Autodesk Fusion 360 part; units mm, degrees
(part 7 of 8)
sketch "Front roller support | profile (2)" plane through (0, 0, 14) normal (0, 0, 1) x (1, 0, 0) in component "11:1 twin-disc elbow | original geometry"
  line L0 (38, 0) -> (37.817, 3.7247)
  line L1 (37.817, 3.7247) -> (37.2698, 7.4134)
  line L2 (37.2698, 7.4134) -> (36.3637, 11.0308)
  line L3 (36.3637, 11.0308) -> (35.1074, 14.542)
  line L4 (35.1074, 14.542) -> (33.513, 17.9131)
  line L5 (33.513, 17.9131) -> (31.5958, 21.1117)
  line L6 (31.5958, 21.1117) -> (29.3744, 24.1069)
  line L7 (29.3744, 24.1069) -> (26.8701, 26.8701)
  line L8 (26.8701, 26.8701) -> (24.1069, 29.3744)
  line L9 (24.1069, 29.3744) -> (21.1117, 31.5958)
  line L10 (21.1117, 31.5958) -> (17.9131, 33.513)
  line L11 (17.9131, 33.513) -> (14.542, 35.1074)
  line L12 (14.542, 35.1074) -> (11.0308, 36.3637)
  line L13 (11.0308, 36.3637) -> (7.4134, 37.2698)
  line L14 (7.4134, 37.2698) -> (3.7247, 37.817)
  line L15 (3.7247, 37.817) -> (0, 38)
  line L16 (0, 38) -> (-3.7247, 37.817)
  line L17 (-3.7247, 37.817) -> (-7.4134, 37.2698)
  line L18 (-7.4134, 37.2698) -> (-11.0308, 36.3637)
  line L19 (-11.0308, 36.3637) -> (-14.542, 35.1074)
  line L20 (-14.542, 35.1074) -> (-17.9131, 33.513)
  line L21 (-17.9131, 33.513) -> (-21.1117, 31.5958)
  line L22 (-21.1117, 31.5958) -> (-24.1069, 29.3744)
  line L23 (-24.1069, 29.3744) -> (-26.8701, 26.8701)
  line L24 (-26.8701, 26.8701) -> (-29.3744, 24.1069)
  line L25 (-29.3744, 24.1069) -> (-31.5958, 21.1117)
  line L26 (-31.5958, 21.1117) -> (-33.513, 17.9131)
  line L27 (-33.513, 17.9131) -> (-35.1074, 14.542)
  line L28 (-35.1074, 14.542) -> (-36.3637, 11.0308)
  line L29 (-36.3637, 11.0308) -> (-37.2698, 7.4134)
  line L30 (-37.2698, 7.4134) -> (-37.817, 3.7247)
  line L31 (-37.817, 3.7247) -> (-38, 0)
  line L32 (-38, 0) -> (-37.817, -3.7247)
  line L33 (-37.817, -3.7247) -> (-37.2698, -7.4134)
  line L34 (-37.2698, -7.4134) -> (-36.3637, -11.0308)
  line L35 (-36.3637, -11.0308) -> (-35.1074, -14.542)
  line L36 (-35.1074, -14.542) -> (-33.513, -17.9131)
  line L37 (-33.513, -17.9131) -> (-31.5958, -21.1117)
  line L38 (-31.5958, -21.1117) -> (-29.3744, -24.1069)
  line L39 (-29.3744, -24.1069) -> (-26.8701, -26.8701)
  line L40 (-26.8701, -26.8701) -> (-24.1069, -29.3744)
  line L41 (-24.1069, -29.3744) -> (-21.1117, -31.5958)
  line L42 (-21.1117, -31.5958) -> (-17.9131, -33.513)
  line L43 (-17.9131, -33.513) -> (-14.542, -35.1074)
  line L44 (-14.542, -35.1074) -> (-11.0308, -36.3637)
  line L45 (-11.0308, -36.3637) -> (-7.4134, -37.2698)
  line L46 (-7.4134, -37.2698) -> (-3.7247, -37.817)
  line L47 (-3.7247, -37.817) -> (0, -38)
  line L48 (0, -38) -> (3.7247, -37.817)
  line L49 (3.7247, -37.817) -> (7.4134, -37.2698)
  line L50 (7.4134, -37.2698) -> (11.0308, -36.3637)
  line L51 (11.0308, -36.3637) -> (14.542, -35.1074)
  line L52 (14.542, -35.1074) -> (17.9131, -33.513)
  line L53 (17.9131, -33.513) -> (21.1117, -31.5958)
  line L54 (21.1117, -31.5958) -> (24.1069, -29.3744)
  line L55 (24.1069, -29.3744) -> (26.8701, -26.8701)
  line L56 (26.8701, -26.8701) -> (29.3744, -24.1069)
  line L57 (29.3744, -24.1069) -> (31.5958, -21.1117)
  line L58 (31.5958, -21.1117) -> (33.513, -17.9131)
  line L59 (33.513, -17.9131) -> (35.1074, -14.542)
  line L60 (35.1074, -14.542) -> (36.3637, -11.0308)
  line L61 (36.3637, -11.0308) -> (37.2698, -7.4134)
  line L62 (37.2698, -7.4134) -> (37.817, -3.7247)
  line L63 (37.817, -3.7247) -> (38, 0)
  circle A0 centre (0, 0) radius 21.1
  circle A1 centre (36, 0) radius 1.6
  circle A2 centre (18, 31.1769) radius 1.6
  circle A3 centre (-18, 31.1769) radius 1.6
  circle A4 centre (-36, 0) radius 1.6
  circle A5 centre (-18, -31.1769) radius 1.6
  circle A6 centre (18, -31.1769) radius 1.6
extrude "Front roller support'" add sketch "Front roller support | profile (2)" along normal blind 3 separate body makes body 323 in component "11:1 twin-disc elbow | original geometry"
ref_plane "WorkPlane4" through (0, 0, -6) normal (0, 0, 1) x (1, 0, 0) in component "11:1 twin-disc elbow | original geometry"
sketch "Cycloidal disc A | 11 lobes | profile (2)" plane through (0, 0, -6) normal (0, 0, 1) x (1, 0, 0) in component "11:1 twin-disc elbow | original geometry"
  spline S0 degree 3 poles (25.9, 0) (25.9, 0.3482) (25.956, 1.0447) (26.1483, 1.9285) (26.3602, 2.6329) (26.553, 3.2163) (26.7189, 3.739) (26.8573, 4.2438) (26.9654, 4.7563) (27.0369, 5.2891) (27.0643, 5.8448) (27.0401, 6.4189) (26.9592, 7.0019) (26.8198, 7.5814) (26.6238, 8.1443) (26.3766, 8.6784) (26.0866, 9.1745) (25.7631, 9.6272) (25.4149, 10.0367) (25.0469, 10.4094) (24.6576, 10.7592) (24.2354, 11.1092) (23.7578, 11.4958) (23.1987, 11.9738) (22.5591, 12.6134) (21.9237, 13.4468) (21.4295, 14.3711) (21.1135, 15.2186) (20.9109, 15.9257) (20.7576, 16.5207) (20.6146, 17.0501) (20.4582, 17.5496) (20.272, 18.0392) (20.0442, 18.5261) (19.7667, 19.0083) (19.436, 19.4782) (19.0528, 19.9249) (18.6222, 20.3371) (18.153, 20.7047) (17.6562, 21.0204) (17.1441, 21.2809) (16.6272, 21.4869) (16.1129, 21.6431) (15.6018, 21.7577) (15.0851, 21.8415) (14.5408, 21.9077) (13.93, 21.9747) (13.2012, 22.0746) (12.3174, 22.2668) (11.3322, 22.6244) (10.4168, 23.1348) (9.6927, 23.6768) (9.14, 24.1622) (8.6894, 24.5799) (8.2829, 24.948) (7.8812, 25.2836) (7.4599, 25.5948) (7.005, 25.8812) (6.5109, 26.1369) (5.9786, 26.3534) (5.4147, 26.522) (4.8297, 26.6359) (4.2362, 26.6914) (3.6476, 26.6885) (3.076, 26.6308) (2.5298, 26.5246) (2.0126, 26.378) (1.5207, 26.1981) (1.0408, 25.9892) (0.547, 25.7506) (-0.003, 25.4768) (-0.6701, 25.1668) (-1.5176, 24.8507) (-2.5397, 24.6188) (-3.5857, 24.5533) (-4.4879, 24.6179) (-5.2153, 24.7274) (-5.8202, 24.8351) (-6.3611, 24.925) (-6.8805, 24.9902) (-7.4031, 25.0242) (-7.9407, 25.0192) (-8.4946, 24.9672) (-9.0594, 24.8615) (-9.625, 24.6985) (-10.1787, 24.478) (-10.708, 24.2039) (-11.2016, 23.8832) (-11.6513, 23.5256) (-12.0534, 23.141) (-12.4091, 22.738) (-12.7257, 22.3207) (-13.0165, 21.8856) (-13.3029, 21.4179) (-13.6176, 20.8902) (-14.0112, 20.2687) (-14.5532, 19.5446) (-15.2877, 18.797) (-16.1322, 18.1764) (-16.9261, 17.7429) (-17.5972, 17.4418) (-18.1644, 17.2054) (-18.6681, 16.9885) (-19.1402, 16.7626) (-19.5983, 16.5086) (-20.0478, 16.2138) (-20.4856, 15.8705) (-20.9037, 15.4763) (-21.2913, 15.0334) (-21.638, 14.5486) (-21.935, 14.0318) (-22.1769, 13.4952) (-22.3618, 12.9512) (-22.4921, 12.4103) (-22.5736, 11.8789) (-22.6143, 11.3567) (-22.6237, 10.8334) (-22.6118, 10.2851) (-22.5912, 9.6711) (-22.5863, 8.9355) (-22.6508, 8.0333) (-22.8645, 7.0073) (-23.2394, 6.0285) (-23.6729, 5.2347) (-24.0747, 4.6185) (-24.424, 4.1131) (-24.7305, 3.6583) (-25.0055, 3.213) (-25.2536, 2.7517) (-25.4723, 2.2606) (-25.6551, 1.7351) (-25.7937, 1.1775) (-25.8803, 0.5953) (-25.9098, 0) (-25.8803, -0.5953) (-25.7937, -1.1775) (-25.6551, -1.7351) (-25.4723, -2.2606) (-25.2536, -2.7517) (-25.0055, -3.213) (-24.7305, -3.6583) (-24.424, -4.1131) (-24.0747, -4.6185) (-23.6729, -5.2347) (-23.2394, -6.0285) (-22.8645, -7.0073) (-22.6508, -8.0333) (-22.5863, -8.9355) (-22.5912, -9.6711) (-22.6118, -10.2851) (-22.6237, -10.8334) (-22.6143, -11.3567) (-22.5736, -11.8789) (-22.4921, -12.4103) (-22.3618, -12.9512) (-22.1769, -13.4952) (-21.935, -14.0318) (-21.638, -14.5486) (-21.2913, -15.0334) (-20.9037, -15.4763) (-20.4856, -15.8705) (-20.0478, -16.2138) (-19.5983, -16.5086) (-19.1402, -16.7626) (-18.6681, -16.9885) (-18.1644, -17.2054) (-17.5972, -17.4418) (-16.9261, -17.7429) (-16.1322, -18.1764) (-15.2877, -18.797) (-14.5532, -19.5446) (-14.0112, -20.2687) (-13.6176, -20.8902) (-13.3029, -21.4179) (-13.0165, -21.8856) (-12.7257, -22.3207) (-12.4091, -22.738) (-12.0534, -23.141) (-11.6513, -23.5256) (-11.2016, -23.8832) (-10.708, -24.2039) (-10.1787, -24.478) (-9.625, -24.6985) (-9.0594, -24.8615) (-8.4946, -24.9672) (-7.9407, -25.0192) (-7.4031, -25.0242) (-6.8805, -24.9902) (-6.3611, -24.925) (-5.8202, -24.8351) (-5.2153, -24.7274) (-4.4879, -24.6179) (-3.5857, -24.5533) (-2.5397, -24.6188) (-1.5176, -24.8507) (-0.6701, -25.1668) (-0.003, -25.4768) (0.547, -25.7506) (1.0408, -25.9892) (1.5207, -26.1981) (2.0126, -26.378) (2.5298, -26.5246) (3.076, -26.6308) (3.6476, -26.6885) (4.2362, -26.6914) (4.8297, -26.6359) (5.4147, -26.522) (5.9786, -26.3534) (6.5109, -26.1369) (7.005, -25.8812) (7.4599, -25.5948) (7.8812, -25.2836) (8.2829, -24.948) (8.6894, -24.5799) (9.14, -24.1622) (9.6927, -23.6768) (10.4168, -23.1348) (11.3322, -22.6244) (12.3174, -22.2668) (13.2012, -22.0746) (13.93, -21.9747) (14.5408, -21.9077) (15.0851, -21.8415) (15.6018, -21.7577) (16.1129, -21.6431) (16.6272, -21.4869) (17.1441, -21.2809) (17.6562, -21.0204) (18.153, -20.7047) (18.6222, -20.3371) (19.0528, -19.9249) (19.436, -19.4782) (19.7667, -19.0083) (20.0442, -18.5261) (20.272, -18.0392) (20.4582, -17.5496) (20.6146, -17.0501) (20.7576, -16.5207) (20.9109, -15.9257) (21.1135, -15.2186) (21.4295, -14.3711) (21.9237, -13.4468) (22.5591, -12.6134) (23.1987, -11.9738) (23.7578, -11.4958) (24.2354, -11.1092) (24.6576, -10.7592) (25.0469, -10.4094) (25.4149, -10.0367) (25.7631, -9.6272) (26.0866, -9.1745) (26.3766, -8.6784) (26.6238, -8.1443) (26.8198, -7.5814) (26.9592, -7.0019) (27.0401, -6.4189) (27.0643, -5.8448) (27.0369, -5.2891) (26.9654, -4.7563) (26.8573, -4.2438) (26.7189, -3.739) (26.553, -3.2163) (26.3602, -2.6329) (26.1483, -1.9285) (25.956, -1.0447) (25.9, -0.3482) (25.9, 0) knots 3 3 3 3 4 5 6 7 8 9 10 11 12 13 14 15 16 17 18 19 20 21 22 23 24 25 26 27 28 29 30 31 32 33 34 35 36 37 38 39 40 41 42 43 44 45 46 47 48 49 50 51 52 53 54 55 56 57 58 59 60 61 62 63 64 65 66 67 68 69 70 71 72 73 74 75 76 77 78 79 80 81 82 83 84 85 86 87 88 89 90 91 92 93 94 95 96 97 98 99 100 101 102 103 104 105 106 107 108 109 110 111 112 113 114 115 116 117 118 119 120 121 122 123 124 125 126 127 128 129 130 131 132 133 134 135 136 137 138 139 140 141 142 143 144 145 146 147 148 149 150 151 152 153 154 155 156 157 158 159 160 161 162 163 164 165 166 167 168 169 170 171 172 173 174 175 176 177 178 179 180 181 182 183 184 185 186 187 188 189 190 191 192 193 194 195 196 197 198 199 200 201 202 203 204 205 206 207 208 209 210 211 212 213 214 215 216 217 218 219 220 221 222 223 224 225 226 227 228 229 230 231 232 233 234 235 236 237 238 239 240 241 242 243 244 245 246 247 248 249 250 251 252 253 254 255 256 257 258 259 260 261 262 263 264 265 266 267 267 267 267
  circle A0 centre (1, 0) radius 9.6
  circle A1 centre (19, 0) radius 2.65
  circle A2 centre (10, 15.5885) radius 2.65
  circle A3 centre (-8, 15.5885) radius 2.65
  circle A4 centre (-17, 0) radius 2.65
  circle A5 centre (-8, -15.5885) radius 2.65
  circle A6 centre (10, -15.5885) radius 2.65
extrude "Cycloidal disc A | 11 lobes'" add sketch "Cycloidal disc A | 11 lobes | profile (2)" along normal blind 5 separate body makes body 324 in component "11:1 twin-disc elbow | original geometry"
ref_plane "WorkPlane5" through (0, 0, -6) normal (0, 0, 1) x (1, 0, 0) in component "11:1 twin-disc elbow | original geometry"
sketch "Eccentric bearing A outer race | profile (2)" plane through (0, 0, -6) normal (0, 0, 1) x (1, 0, 0) in component "11:1 twin-disc elbow | original geometry"
  circle A0 centre (1, 0) radius 9.5
  circle A1 centre (1, 0) radius 8.5
extrude "Eccentric bearing A outer race'" add sketch "Eccentric bearing A outer race | profile (2)" along normal blind 5 separate body makes body 325 in component "11:1 twin-disc elbow | original geometry"
ref_plane "WorkPlane6" through (0, 0, -6) normal (0, 0, 1) x (1, 0, 0) in component "11:1 twin-disc elbow | original geometry"
sketch "Eccentric bearing A inner race | profile (2)" plane through (0, 0, -6) normal (0, 0, 1) x (1, 0, 0) in component "11:1 twin-disc elbow | original geometry"
  circle A0 centre (1, 0) radius 6
  circle A1 centre (1, 0) radius 5
extrude "Eccentric bearing A inner race'" add sketch "Eccentric bearing A inner race | profile (2)" along normal blind 5 separate body makes body 326 in component "11:1 twin-disc elbow | original geometry"
ref_plane "WorkPlane7" through (0, 0, -5.85) normal (0, 0, 1) x (1, 0, 0) in component "11:1 twin-disc elbow | original geometry"
sketch "Eccentric bearing A shield | profile (2)" plane through (0, 0, -5.85) normal (0, 0, 1) x (1, 0, 0) in component "11:1 twin-disc elbow | original geometry"
  circle A0 centre (1, 0) radius 8.5
  circle A1 centre (1, 0) radius 6
extrude "Eccentric bearing A shield'" add sketch "Eccentric bearing A shield | profile (2)" along normal blind 4.7 separate body makes body 327 in component "11:1 twin-disc elbow | original geometry"
ref_plane "WorkPlane8" through (0, 0, -6) normal (0, 0, 1) x (1, 0, 0) in component "11:1 twin-disc elbow | original geometry"
sketch "Steel eccentric cam A | profile (2)" plane through (0, 0, -6) normal (0, 0, 1) x (1, 0, 0) in component "11:1 twin-disc elbow | original geometry"
  circle A0 centre (1, 0) radius 5
  circle A1 centre (1, 0) radius 3
extrude "Steel eccentric cam A'" add sketch "Steel eccentric cam A | profile (2)" along normal blind 5 separate body makes body 328 in component "11:1 twin-disc elbow | original geometry"
ref_plane "WorkPlane9" through (0, 0, 1) normal (0, 0, 1) x (1, 0, 0) in component "11:1 twin-disc elbow | original geometry"
sketch "Cycloidal disc B | 11 lobes | profile (2)" plane through (0, 0, 1) normal (0, 0, 1) x (1, 0, 0) in component "11:1 twin-disc elbow | original geometry"
  spline S0 degree 3 poles (22.8914, -7.0151) (22.9895, -6.681) (23.2394, -6.0285) (23.6729, -5.2347) (24.0747, -4.6185) (24.424, -4.1131) (24.7305, -3.6583) (25.0055, -3.213) (25.2536, -2.7517) (25.4723, -2.2606) (25.6551, -1.7351) (25.7937, -1.1775) (25.8803, -0.5953) (25.9098, 0) (25.8803, 0.5953) (25.7937, 1.1775) (25.6551, 1.7351) (25.4723, 2.2606) (25.2536, 2.7517) (25.0055, 3.213) (24.7305, 3.6583) (24.424, 4.1131) (24.0747, 4.6185) (23.6729, 5.2347) (23.2394, 6.0285) (22.8645, 7.0073) (22.6508, 8.0333) (22.5863, 8.9355) (22.5912, 9.6711) (22.6118, 10.2851) (22.6237, 10.8334) (22.6143, 11.3567) (22.5736, 11.8789) (22.4921, 12.4103) (22.3618, 12.9512) (22.1769, 13.4952) (21.935, 14.0318) (21.638, 14.5486) (21.2913, 15.0334) (20.9037, 15.4763) (20.4856, 15.8705) (20.0478, 16.2138) (19.5983, 16.5086) (19.1402, 16.7626) (18.6681, 16.9885) (18.1644, 17.2054) (17.5972, 17.4418) (16.9261, 17.7429) (16.1322, 18.1764) (15.2877, 18.797) (14.5532, 19.5446) (14.0112, 20.2687) (13.6176, 20.8902) (13.3029, 21.4179) (13.0165, 21.8856) (12.7257, 22.3207) (12.4091, 22.738) (12.0534, 23.141) (11.6513, 23.5256) (11.2016, 23.8832) (10.708, 24.2039) (10.1787, 24.478) (9.625, 24.6985) (9.0594, 24.8615) (8.4946, 24.9672) (7.9407, 25.0192) (7.4031, 25.0242) (6.8805, 24.9902) (6.3611, 24.925) (5.8202, 24.8351) (5.2153, 24.7274) (4.4879, 24.6179) (3.5857, 24.5533) (2.5397, 24.6188) (1.5176, 24.8507) (0.6701, 25.1668) (0.003, 25.4768) (-0.547, 25.7506) (-1.0408, 25.9892) (-1.5207, 26.1981) (-2.0126, 26.378) (-2.5298, 26.5246) (-3.076, 26.6308) (-3.6476, 26.6885) (-4.2362, 26.6914) (-4.8297, 26.6359) (-5.4147, 26.522) (-5.9786, 26.3534) (-6.5109, 26.1369) (-7.005, 25.8812) (-7.4599, 25.5948) (-7.8812, 25.2836) (-8.2829, 24.948) (-8.6894, 24.5799) (-9.14, 24.1622) (-9.6927, 23.6768) (-10.4168, 23.1348) (-11.3322, 22.6244) (-12.3174, 22.2668) (-13.2012, 22.0746) (-13.93, 21.9747) (-14.5408, 21.9077) (-15.0851, 21.8415) (-15.6018, 21.7577) (-16.1129, 21.6431) (-16.6272, 21.4869) (-17.1441, 21.2809) (-17.6562, 21.0204) (-18.153, 20.7047) (-18.6222, 20.3371) (-19.0528, 19.9249) (-19.436, 19.4782) (-19.7667, 19.0083) (-20.0442, 18.5261) (-20.272, 18.0392) (-20.4582, 17.5496) (-20.6146, 17.0501) (-20.7576, 16.5207) (-20.9109, 15.9257) (-21.1135, 15.2186) (-21.4295, 14.3711) (-21.9237, 13.4468) (-22.5591, 12.6134) (-23.1987, 11.9738) (-23.7578, 11.4958) (-24.2354, 11.1092) (-24.6576, 10.7592) (-25.0469, 10.4094) (-25.4149, 10.0367) (-25.7631, 9.6272) (-26.0866, 9.1745) (-26.3766, 8.6784) (-26.6238, 8.1443) (-26.8198, 7.5814) (-26.9592, 7.0019) (-27.0401, 6.4189) (-27.0643, 5.8448) (-27.0369, 5.2891) (-26.9654, 4.7563) (-26.8573, 4.2438) (-26.7189, 3.739) (-26.553, 3.2163) (-26.3602, 2.6329) (-26.1483, 1.9285) (-25.956, 1.0447) (-25.872, 0) (-25.956, -1.0447) (-26.1483, -1.9285) (-26.3602, -2.6329) (-26.553, -3.2163) (-26.7189, -3.739) (-26.8573, -4.2438) (-26.9654, -4.7563) (-27.0369, -5.2891) (-27.0643, -5.8448) (-27.0401, -6.4189) (-26.9592, -7.0019) (-26.8198, -7.5814) (-26.6238, -8.1443) (-26.3766, -8.6784) (-26.0866, -9.1745) (-25.7631, -9.6272) (-25.4149, -10.0367) (-25.0469, -10.4094) (-24.6576, -10.7592) (-24.2354, -11.1092) (-23.7578, -11.4958) (-23.1987, -11.9738) (-22.5591, -12.6134) (-21.9237, -13.4468) (-21.4295, -14.3711) (-21.1135, -15.2186) (-20.9109, -15.9257) (-20.7576, -16.5207) (-20.6146, -17.0501) (-20.4582, -17.5496) (-20.272, -18.0392) (-20.0442, -18.5261) (-19.7667, -19.0083) (-19.436, -19.4782) (-19.0528, -19.9249) (-18.6222, -20.3371) (-18.153, -20.7047) (-17.6562, -21.0204) (-17.1441, -21.2809) (-16.6272, -21.4869) (-16.1129, -21.6431) (-15.6018, -21.7577) (-15.0851, -21.8415) (-14.5408, -21.9077) (-13.93, -21.9747) (-13.2012, -22.0746) (-12.3174, -22.2668) (-11.3322, -22.6244) (-10.4168, -23.1348) (-9.6927, -23.6768) (-9.14, -24.1622) (-8.6894, -24.5799) (-8.2829, -24.948) (-7.8812, -25.2836) (-7.4599, -25.5948) (-7.005, -25.8812) (-6.5109, -26.1369) (-5.9786, -26.3534) (-5.4147, -26.522) (-4.8297, -26.6359) (-4.2362, -26.6914) (-3.6476, -26.6885) (-3.076, -26.6308) (-2.5298, -26.5246) (-2.0126, -26.378) (-1.5207, -26.1981) (-1.0408, -25.9892) (-0.547, -25.7506) (0.003, -25.4768) (0.6701, -25.1668) (1.5176, -24.8507) (2.5397, -24.6188) (3.5857, -24.5533) (4.4879, -24.6179) (5.2153, -24.7274) (5.8202, -24.8351) (6.3611, -24.925) (6.8805, -24.9902) (7.4031, -25.0242) (7.9407, -25.0192) (8.4946, -24.9672) (9.0594, -24.8615) (9.625, -24.6985) (10.1787, -24.478) (10.708, -24.2039) (11.2016, -23.8832) (11.6513, -23.5256) (12.0534, -23.141) (12.4091, -22.738) (12.7257, -22.3207) (13.0165, -21.8856) (13.3029, -21.4179) (13.6176, -20.8902) (14.0112, -20.2687) (14.5532, -19.5446) (15.2877, -18.797) (16.1322, -18.1764) (16.9261, -17.7429) (17.5972, -17.4418) (18.1644, -17.2054) (18.6681, -16.9885) (19.1402, -16.7626) (19.5983, -16.5086) (20.0478, -16.2138) (20.4856, -15.8705) (20.9037, -15.4763) (21.2913, -15.0334) (21.638, -14.5486) (21.935, -14.0318) (22.1769, -13.4952) (22.3618, -12.9512) (22.4921, -12.4103) (22.5736, -11.8789) (22.6143, -11.3567) (22.6237, -10.8334) (22.6118, -10.2851) (22.5912, -9.6711) (22.5863, -8.9355) (22.6508, -8.0333) (22.7933, -7.3493) (22.8914, -7.0151) knots 3 3 3 3 4 5 6 7 8 9 10 11 12 13 14 15 16 17 18 19 20 21 22 23 24 25 26 27 28 29 30 31 32 33 34 35 36 37 38 39 40 41 42 43 44 45 46 47 48 49 50 51 52 53 54 55 56 57 58 59 60 61 62 63 64 65 66 67 68 69 70 71 72 73 74 75 76 77 78 79 80 81 82 83 84 85 86 87 88 89 90 91 92 93 94 95 96 97 98 99 100 101 102 103 104 105 106 107 108 109 110 111 112 113 114 115 116 117 118 119 120 121 122 123 124 125 126 127 128 129 130 131 132 133 134 135 136 137 138 139 140 141 142 143 144 145 146 147 148 149 150 151 152 153 154 155 156 157 158 159 160 161 162 163 164 165 166 167 168 169 170 171 172 173 174 175 176 177 178 179 180 181 182 183 184 185 186 187 188 189 190 191 192 193 194 195 196 197 198 199 200 201 202 203 204 205 206 207 208 209 210 211 212 213 214 215 216 217 218 219 220 221 222 223 224 225 226 227 228 229 230 231 232 233 234 235 236 237 238 239 240 241 242 243 244 245 246 247 248 249 250 251 252 253 254 255 256 257 258 259 260 261 262 263 264 265 266 267 267 267 267
  circle A0 centre (-1, 0) radius 9.6
  circle A1 centre (17, 0) radius 2.65
  circle A2 centre (8, 15.5885) radius 2.65
  circle A3 centre (-10, 15.5885) radius 2.65
  circle A4 centre (-19, 0) radius 2.65
  circle A5 centre (-10, -15.5885) radius 2.65
  circle A6 centre (8, -15.5885) radius 2.65
extrude "Cycloidal disc B | 11 lobes'" add sketch "Cycloidal disc B | 11 lobes | profile (2)" along normal blind 5 separate body makes body 329 in component "11:1 twin-disc elbow | original geometry"
ref_plane "WorkPlane10" through (0, 0, 1) normal (0, 0, 1) x (1, 0, 0) in component "11:1 twin-disc elbow | original geometry"
sketch "Eccentric bearing B outer race | profile (2)" plane through (0, 0, 1) normal (0, 0, 1) x (1, 0, 0) in component "11:1 twin-disc elbow | original geometry"
  circle A0 centre (-1, 0) radius 9.5
  circle A1 centre (-1, 0) radius 8.5
extrude "Eccentric bearing B outer race'" add sketch "Eccentric bearing B outer race | profile (2)" along normal blind 5 separate body makes body 330 in component "11:1 twin-disc elbow | original geometry"
ref_plane "WorkPlane11" through (0, 0, 1) normal (0, 0, 1) x (1, 0, 0) in component "11:1 twin-disc elbow | original geometry"
sketch "Eccentric bearing B inner race | profile (2)" plane through (0, 0, 1) normal (0, 0, 1) x (1, 0, 0) in component "11:1 twin-disc elbow | original geometry"
  circle A0 centre (-1, 0) radius 6
  circle A1 centre (-1, 0) radius 5
extrude "Eccentric bearing B inner race'" add sketch "Eccentric bearing B inner race | profile (2)" along normal blind 5 separate body makes body 331 in component "11:1 twin-disc elbow | original geometry"
ref_plane "WorkPlane12" through (0, 0, 1.15) normal (0, 0, 1) x (1, 0, 0) in component "11:1 twin-disc elbow | original geometry"
sketch "Eccentric bearing B shield | profile (2)" plane through (0, 0, 1.15) normal (0, 0, 1) x (1, 0, 0) in component "11:1 twin-disc elbow | original geometry"
  circle A0 centre (-1, 0) radius 8.5
  circle A1 centre (-1, 0) radius 6
extrude "Eccentric bearing B shield'" add sketch "Eccentric bearing B shield | profile (2)" along normal blind 4.7 separate body makes body 332 in component "11:1 twin-disc elbow | original geometry"
ref_plane "WorkPlane13" through (0, 0, 1) normal (0, 0, 1) x (1, 0, 0) in component "11:1 twin-disc elbow | original geometry"
sketch "Steel eccentric cam B | profile (2)" plane through (0, 0, 1) normal (0, 0, 1) x (1, 0, 0) in component "11:1 twin-disc elbow | original geometry"
  circle A0 centre (-1, 0) radius 5
  circle A1 centre (-1, 0) radius 3
extrude "Steel eccentric cam B'" add sketch "Steel eccentric cam B | profile (2)" along normal blind 5 separate body makes body 333 in component "11:1 twin-disc elbow | original geometry"
ref_plane "WorkPlane14" through (0, 0, -17) normal (0, 0, 1) x (1, 0, 0) in component "11:1 twin-disc elbow | original geometry"
sketch "Fixed metal roller pin 1 | profile (2)" plane through (0, 0, -17) normal (0, 0, 1) x (1, 0, 0) in component "11:1 twin-disc elbow | original geometry"
  circle A0 centre (30, 0) radius 1.5
extrude "Fixed metal roller pin 1'" add sketch "Fixed metal roller pin 1 | profile (2)" along normal blind 34 separate body makes body 334 in component "11:1 twin-disc elbow | original geometry"
ref_plane "WorkPlane15" through (0, 0, -6) normal (0, 0, 1) x (1, 0, 0) in component "11:1 twin-disc elbow | original geometry"
sketch "693ZZ outer race | profile" plane through (0, 0, -6) normal (0, 0, 1) x (1, 0, 0) in component "11:1 twin-disc elbow | original geometry"
  circle A0 centre (30, 0) radius 4
  circle A1 centre (30, 0) radius 3
extrude "693ZZ outer race" add sketch "693ZZ outer race | profile" along normal blind 4 separate body makes body 335 in component "11:1 twin-disc elbow | original geometry"
ref_plane "WorkPlane16" through (0, 0, -6) normal (0, 0, 1) x (1, 0, 0) in component "11:1 twin-disc elbow | original geometry"
sketch "693ZZ inner race | profile" plane through (0, 0, -6) normal (0, 0, 1) x (1, 0, 0) in component "11:1 twin-disc elbow | original geometry"
  circle A0 centre (30, 0) radius 2.5
  circle A1 centre (30, 0) radius 1.5
extrude "693ZZ inner race" add sketch "693ZZ inner race | profile" along normal blind 4 separate body makes body 336 in component "11:1 twin-disc elbow | original geometry"
ref_plane "WorkPlane17" through (0, 0, -5.85) normal (0, 0, 1) x (1, 0, 0) in component "11:1 twin-disc elbow | original geometry"
sketch "693ZZ shield | profile" plane through (0, 0, -5.85) normal (0, 0, 1) x (1, 0, 0) in component "11:1 twin-disc elbow | original geometry"
  circle A0 centre (30, 0) radius 3
  circle A1 centre (30, 0) radius 2.5
extrude "693ZZ shield" add sketch "693ZZ shield | profile" along normal blind 3.7 separate body makes body 337 in component "11:1 twin-disc elbow | original geometry"
ref_plane "WorkPlane18" through (0, 0, 2) normal (0, 0, 1) x (1, 0, 0) in component "11:1 twin-disc elbow | original geometry"
sketch "693ZZ outer race | profile (1)" plane through (0, 0, 2) normal (0, 0, 1) x (1, 0, 0) in component "11:1 twin-disc elbow | original geometry"
  circle A0 centre (30, 0) radius 4
  circle A1 centre (30, 0) radius 3
extrude "693ZZ outer race (1)" add sketch "693ZZ outer race | profile (1)" along normal blind 4 separate body makes body 338 in component "11:1 twin-disc elbow | original geometry"
ref_plane "WorkPlane19" through (0, 0, 2) normal (0, 0, 1) x (1, 0, 0) in component "11:1 twin-disc elbow | original geometry"
sketch "693ZZ inner race | profile (1)" plane through (0, 0, 2) normal (0, 0, 1) x (1, 0, 0) in component "11:1 twin-disc elbow | original geometry"
  circle A0 centre (30, 0) radius 2.5
  circle A1 centre (30, 0) radius 1.5
extrude "693ZZ inner race (1)" add sketch "693ZZ inner race | profile (1)" along normal blind 4 separate body makes body 339 in component "11:1 twin-disc elbow | original geometry"
ref_plane "WorkPlane20" through (0, 0, 2.15) normal (0, 0, 1) x (1, 0, 0) in component "11:1 twin-disc elbow | original geometry"
sketch "693ZZ shield | profile (1)" plane through (0, 0, 2.15) normal (0, 0, 1) x (1, 0, 0) in component "11:1 twin-disc elbow | original geometry"
  circle A0 centre (30, 0) radius 3
  circle A1 centre (30, 0) radius 2.5
extrude "693ZZ shield (1)" add sketch "693ZZ shield | profile (1)" along normal blind 3.7 separate body makes body 340 in component "11:1 twin-disc elbow | original geometry"
ref_plane "WorkPlane21" through (0, 0, -17) normal (0, 0, 1) x (1, 0, 0) in component "11:1 twin-disc elbow | original geometry"
sketch "Fixed metal roller pin 2 | profile (2)" plane through (0, 0, -17) normal (0, 0, 1) x (1, 0, 0) in component "11:1 twin-disc elbow | original geometry"
  circle A0 centre (25.9808, 15) radius 1.5
extrude "Fixed metal roller pin 2'" add sketch "Fixed metal roller pin 2 | profile (2)" along normal blind 34 separate body makes body 341 in component "11:1 twin-disc elbow | original geometry"
ref_plane "WorkPlane22" through (0, 0, -6) normal (0, 0, 1) x (1, 0, 0) in component "11:1 twin-disc elbow | original geometry"
sketch "693ZZ outer race | profile (2)" plane through (0, 0, -6) normal (0, 0, 1) x (1, 0, 0) in component "11:1 twin-disc elbow | original geometry"
  circle A0 centre (25.9808, 15) radius 4
  circle A1 centre (25.9808, 15) radius 3
extrude "693ZZ outer race (2)" add sketch "693ZZ outer race | profile (2)" along normal blind 4 separate body makes body 342 in component "11:1 twin-disc elbow | original geometry"
ref_plane "WorkPlane23" through (0, 0, -6) normal (0, 0, 1) x (1, 0, 0) in component "11:1 twin-disc elbow | original geometry"
sketch "693ZZ inner race | profile (2)" plane through (0, 0, -6) normal (0, 0, 1) x (1, 0, 0) in component "11:1 twin-disc elbow | original geometry"
  circle A0 centre (25.9808, 15) radius 2.5
  circle A1 centre (25.9808, 15) radius 1.5
extrude "693ZZ inner race (2)" add sketch "693ZZ inner race | profile (2)" along normal blind 4 separate body makes body 343 in component "11:1 twin-disc elbow | original geometry"
ref_plane "WorkPlane24" through (0, 0, -5.85) normal (0, 0, 1) x (1, 0, 0) in component "11:1 twin-disc elbow | original geometry"
sketch "693ZZ shield | profile (2)" plane through (0, 0, -5.85) normal (0, 0, 1) x (1, 0, 0) in component "11:1 twin-disc elbow | original geometry"
  circle A0 centre (25.9808, 15) radius 3
  circle A1 centre (25.9808, 15) radius 2.5
extrude "693ZZ shield (2)" add sketch "693ZZ shield | profile (2)" along normal blind 3.7 separate body makes body 344 in component "11:1 twin-disc elbow | original geometry"
ref_plane "WorkPlane25" through (0, 0, 2) normal (0, 0, 1) x (1, 0, 0) in component "11:1 twin-disc elbow | original geometry"
sketch "693ZZ outer race | profile (3)" plane through (0, 0, 2) normal (0, 0, 1) x (1, 0, 0) in component "11:1 twin-disc elbow | original geometry"
  circle A0 centre (25.9808, 15) radius 4
  circle A1 centre (25.9808, 15) radius 3
extrude "693ZZ outer race (3)" add sketch "693ZZ outer race | profile (3)" along normal blind 4 separate body makes body 345 in component "11:1 twin-disc elbow | original geometry"
ref_plane "WorkPlane26" through (0, 0, 2) normal (0, 0, 1) x (1, 0, 0) in component "11:1 twin-disc elbow | original geometry"
sketch "693ZZ inner race | profile (3)" plane through (0, 0, 2) normal (0, 0, 1) x (1, 0, 0) in component "11:1 twin-disc elbow | original geometry"
  circle A0 centre (25.9808, 15) radius 2.5
  circle A1 centre (25.9808, 15) radius 1.5
extrude "693ZZ inner race (3)" add sketch "693ZZ inner race | profile (3)" along normal blind 4 separate body makes body 346 in component "11:1 twin-disc elbow | original geometry"
ref_plane "WorkPlane27" through (0, 0, 2.15) normal (0, 0, 1) x (1, 0, 0) in component "11:1 twin-disc elbow | original geometry"
sketch "693ZZ shield | profile (3)" plane through (0, 0, 2.15) normal (0, 0, 1) x (1, 0, 0) in component "11:1 twin-disc elbow | original geometry"
  circle A0 centre (25.9808, 15) radius 3
  circle A1 centre (25.9808, 15) radius 2.5
extrude "693ZZ shield (3)" add sketch "693ZZ shield | profile (3)" along normal blind 3.7 separate body makes body 347 in component "11:1 twin-disc elbow | original geometry"
ref_plane "WorkPlane28" through (0, 0, -17) normal (0, 0, 1) x (1, 0, 0) in component "11:1 twin-disc elbow | original geometry"
sketch "Fixed metal roller pin 3 | profile (2)" plane through (0, 0, -17) normal (0, 0, 1) x (1, 0, 0) in component "11:1 twin-disc elbow | original geometry"
  circle A0 centre (15, 25.9808) radius 1.5
extrude "Fixed metal roller pin 3'" add sketch "Fixed metal roller pin 3 | profile (2)" along normal blind 34 separate body makes body 348 in component "11:1 twin-disc elbow | original geometry"
ref_plane "WorkPlane29" through (0, 0, -6) normal (0, 0, 1) x (1, 0, 0) in component "11:1 twin-disc elbow | original geometry"
sketch "693ZZ outer race | profile (4)" plane through (0, 0, -6) normal (0, 0, 1) x (1, 0, 0) in component "11:1 twin-disc elbow | original geometry"
  circle A0 centre (15, 25.9808) radius 4
  circle A1 centre (15, 25.9808) radius 3
extrude "693ZZ outer race (4)" add sketch "693ZZ outer race | profile (4)" along normal blind 4 separate body makes body 349 in component "11:1 twin-disc elbow | original geometry"
ref_plane "WorkPlane30" through (0, 0, -6) normal (0, 0, 1) x (1, 0, 0) in component "11:1 twin-disc elbow | original geometry"
sketch "693ZZ inner race | profile (4)" plane through (0, 0, -6) normal (0, 0, 1) x (1, 0, 0) in component "11:1 twin-disc elbow | original geometry"
  circle A0 centre (15, 25.9808) radius 2.5
  circle A1 centre (15, 25.9808) radius 1.5
extrude "693ZZ inner race (4)" add sketch "693ZZ inner race | profile (4)" along normal blind 4 separate body makes body 350 in component "11:1 twin-disc elbow | original geometry"
ref_plane "WorkPlane31" through (0, 0, -5.85) normal (0, 0, 1) x (1, 0, 0) in component "11:1 twin-disc elbow | original geometry"
sketch "693ZZ shield | profile (4)" plane through (0, 0, -5.85) normal (0, 0, 1) x (1, 0, 0) in component "11:1 twin-disc elbow | original geometry"
  circle A0 centre (15, 25.9808) radius 3
  circle A1 centre (15, 25.9808) radius 2.5
extrude "693ZZ shield (4)" add sketch "693ZZ shield | profile (4)" along normal blind 3.7 separate body makes body 351 in component "11:1 twin-disc elbow | original geometry"
ref_plane "WorkPlane32" through (0, 0, 2) normal (0, 0, 1) x (1, 0, 0) in component "11:1 twin-disc elbow | original geometry"
sketch "693ZZ outer race | profile (5)" plane through (0, 0, 2) normal (0, 0, 1) x (1, 0, 0) in component "11:1 twin-disc elbow | original geometry"
  circle A0 centre (15, 25.9808) radius 4
  circle A1 centre (15, 25.9808) radius 3
extrude "693ZZ outer race (5)" add sketch "693ZZ outer race | profile (5)" along normal blind 4 separate body makes body 352 in component "11:1 twin-disc elbow | original geometry"
ref_plane "WorkPlane33" through (0, 0, 2) normal (0, 0, 1) x (1, 0, 0) in component "11:1 twin-disc elbow | original geometry"
sketch "693ZZ inner race | profile (5)" plane through (0, 0, 2) normal (0, 0, 1) x (1, 0, 0) in component "11:1 twin-disc elbow | original geometry"
  circle A0 centre (15, 25.9808) radius 2.5
  circle A1 centre (15, 25.9808) radius 1.5
extrude "693ZZ inner race (5)" add sketch "693ZZ inner race | profile (5)" along normal blind 4 separate body makes body 353 in component "11:1 twin-disc elbow | original geometry"
ref_plane "WorkPlane34" through (0, 0, 2.15) normal (0, 0, 1) x (1, 0, 0) in component "11:1 twin-disc elbow | original geometry"
sketch "693ZZ shield | profile (5)" plane through (0, 0, 2.15) normal (0, 0, 1) x (1, 0, 0) in component "11:1 twin-disc elbow | original geometry"
  circle A0 centre (15, 25.9808) radius 3
  circle A1 centre (15, 25.9808) radius 2.5
extrude "693ZZ shield (5)" add sketch "693ZZ shield | profile (5)" along normal blind 3.7 separate body makes body 354 in component "11:1 twin-disc elbow | original geometry"
ref_plane "WorkPlane35" through (0, 0, -17) normal (0, 0, 1) x (1, 0, 0) in component "11:1 twin-disc elbow | original geometry"
sketch "Fixed metal roller pin 4 | profile (2)" plane through (0, 0, -17) normal (0, 0, 1) x (1, 0, 0) in component "11:1 twin-disc elbow | original geometry"
  circle A0 centre (0, 30) radius 1.5
extrude "Fixed metal roller pin 4'" add sketch "Fixed metal roller pin 4 | profile (2)" along normal blind 34 separate body makes body 355 in component "11:1 twin-disc elbow | original geometry"
ref_plane "WorkPlane36" through (0, 0, -6) normal (0, 0, 1) x (1, 0, 0) in component "11:1 twin-disc elbow | original geometry"
sketch "693ZZ outer race | profile (6)" plane through (0, 0, -6) normal (0, 0, 1) x (1, 0, 0) in component "11:1 twin-disc elbow | original geometry"
  circle A0 centre (0, 30) radius 4
  circle A1 centre (0, 30) radius 3
extrude "693ZZ outer race (6)" add sketch "693ZZ outer race | profile (6)" along normal blind 4 separate body makes body 356 in component "11:1 twin-disc elbow | original geometry"
ref_plane "WorkPlane37" through (0, 0, -6) normal (0, 0, 1) x (1, 0, 0) in component "11:1 twin-disc elbow | original geometry"
sketch "693ZZ inner race | profile (6)" plane through (0, 0, -6) normal (0, 0, 1) x (1, 0, 0) in component "11:1 twin-disc elbow | original geometry"
  circle A0 centre (0, 30) radius 2.5
  circle A1 centre (0, 30) radius 1.5
extrude "693ZZ inner race (6)" add sketch "693ZZ inner race | profile (6)" along normal blind 4 separate body makes body 357 in component "11:1 twin-disc elbow | original geometry"
ref_plane "WorkPlane38" through (0, 0, -5.85) normal (0, 0, 1) x (1, 0, 0) in component "11:1 twin-disc elbow | original geometry"
sketch "693ZZ shield | profile (6)" plane through (0, 0, -5.85) normal (0, 0, 1) x (1, 0, 0) in component "11:1 twin-disc elbow | original geometry"
  circle A0 centre (0, 30) radius 3
  circle A1 centre (0, 30) radius 2.5
extrude "693ZZ shield (6)" add sketch "693ZZ shield | profile (6)" along normal blind 3.7 separate body makes body 358 in component "11:1 twin-disc elbow | original geometry"
ref_plane "WorkPlane39" through (0, 0, 2) normal (0, 0, 1) x (1, 0, 0) in component "11:1 twin-disc elbow | original geometry"
sketch "693ZZ outer race | profile (7)" plane through (0, 0, 2) normal (0, 0, 1) x (1, 0, 0) in component "11:1 twin-disc elbow | original geometry"
  circle A0 centre (0, 30) radius 4
  circle A1 centre (0, 30) radius 3
extrude "693ZZ outer race (7)" add sketch "693ZZ outer race | profile (7)" along normal blind 4 separate body makes body 359 in component "11:1 twin-disc elbow | original geometry"
ref_plane "WorkPlane40" through (0, 0, 2) normal (0, 0, 1) x (1, 0, 0) in component "11:1 twin-disc elbow | original geometry"
sketch "693ZZ inner race | profile (7)" plane through (0, 0, 2) normal (0, 0, 1) x (1, 0, 0) in component "11:1 twin-disc elbow | original geometry"
  circle A0 centre (0, 30) radius 2.5
  circle A1 centre (0, 30) radius 1.5
extrude "693ZZ inner race (7)" add sketch "693ZZ inner race | profile (7)" along normal blind 4 separate body makes body 360 in component "11:1 twin-disc elbow | original geometry"
ref_plane "WorkPlane41" through (0, 0, 2.15) normal (0, 0, 1) x (1, 0, 0) in component "11:1 twin-disc elbow | original geometry"
sketch "693ZZ shield | profile (7)" plane through (0, 0, 2.15) normal (0, 0, 1) x (1, 0, 0) in component "11:1 twin-disc elbow | original geometry"
  circle A0 centre (0, 30) radius 3
  circle A1 centre (0, 30) radius 2.5
extrude "693ZZ shield (7)" add sketch "693ZZ shield | profile (7)" along normal blind 3.7 separate body makes body 361 in component "11:1 twin-disc elbow | original geometry"
ref_plane "WorkPlane42" through (0, 0, -17) normal (0, 0, 1) x (1, 0, 0) in component "11:1 twin-disc elbow | original geometry"
sketch "Fixed metal roller pin 5 | profile (2)" plane through (0, 0, -17) normal (0, 0, 1) x (1, 0, 0) in component "11:1 twin-disc elbow | original geometry"
  circle A0 centre (-15, 25.9808) radius 1.5
extrude "Fixed metal roller pin 5'" add sketch "Fixed metal roller pin 5 | profile (2)" along normal blind 34 separate body makes body 362 in component "11:1 twin-disc elbow | original geometry"
ref_plane "WorkPlane43" through (0, 0, -6) normal (0, 0, 1) x (1, 0, 0) in component "11:1 twin-disc elbow | original geometry"
sketch "693ZZ outer race | profile (8)" plane through (0, 0, -6) normal (0, 0, 1) x (1, 0, 0) in component "11:1 twin-disc elbow | original geometry"
  circle A0 centre (-15, 25.9808) radius 4
  circle A1 centre (-15, 25.9808) radius 3
extrude "693ZZ outer race (8)" add sketch "693ZZ outer race | profile (8)" along normal blind 4 separate body makes body 363 in component "11:1 twin-disc elbow | original geometry"
ref_plane "WorkPlane44" through (0, 0, -6) normal (0, 0, 1) x (1, 0, 0) in component "11:1 twin-disc elbow | original geometry"
sketch "693ZZ inner race | profile (8)" plane through (0, 0, -6) normal (0, 0, 1) x (1, 0, 0) in component "11:1 twin-disc elbow | original geometry"
  circle A0 centre (-15, 25.9808) radius 2.5
  circle A1 centre (-15, 25.9808) radius 1.5
extrude "693ZZ inner race (8)" add sketch "693ZZ inner race | profile (8)" along normal blind 4 separate body makes body 364 in component "11:1 twin-disc elbow | original geometry"
ref_plane "WorkPlane45" through (0, 0, -5.85) normal (0, 0, 1) x (1, 0, 0) in component "11:1 twin-disc elbow | original geometry"
sketch "693ZZ shield | profile (8)" plane through (0, 0, -5.85) normal (0, 0, 1) x (1, 0, 0) in component "11:1 twin-disc elbow | original geometry"
  circle A0 centre (-15, 25.9808) radius 3
  circle A1 centre (-15, 25.9808) radius 2.5
extrude "693ZZ shield (8)" add sketch "693ZZ shield | profile (8)" along normal blind 3.7 separate body makes body 365 in component "11:1 twin-disc elbow | original geometry"
ref_plane "WorkPlane46" through (0, 0, 2) normal (0, 0, 1) x (1, 0, 0) in component "11:1 twin-disc elbow | original geometry"
sketch "693ZZ outer race | profile (9)" plane through (0, 0, 2) normal (0, 0, 1) x (1, 0, 0) in component "11:1 twin-disc elbow | original geometry"
  circle A0 centre (-15, 25.9808) radius 4
  circle A1 centre (-15, 25.9808) radius 3
extrude "693ZZ outer race (9)" add sketch "693ZZ outer race | profile (9)" along normal blind 4 separate body makes body 366 in component "11:1 twin-disc elbow | original geometry"
ref_plane "WorkPlane47" through (0, 0, 2) normal (0, 0, 1) x (1, 0, 0) in component "11:1 twin-disc elbow | original geometry"
sketch "693ZZ inner race | profile (9)" plane through (0, 0, 2) normal (0, 0, 1) x (1, 0, 0) in component "11:1 twin-disc elbow | original geometry"
  circle A0 centre (-15, 25.9808) radius 2.5
  circle A1 centre (-15, 25.9808) radius 1.5
extrude "693ZZ inner race (9)" add sketch "693ZZ inner race | profile (9)" along normal blind 4 separate body makes body 367 in component "11:1 twin-disc elbow | original geometry"
ref_plane "WorkPlane48" through (0, 0, 2.15) normal (0, 0, 1) x (1, 0, 0) in component "11:1 twin-disc elbow | original geometry"
sketch "693ZZ shield | profile (9)" plane through (0, 0, 2.15) normal (0, 0, 1) x (1, 0, 0) in component "11:1 twin-disc elbow | original geometry"
  circle A0 centre (-15, 25.9808) radius 3
  circle A1 centre (-15, 25.9808) radius 2.5
extrude "693ZZ shield (9)" add sketch "693ZZ shield | profile (9)" along normal blind 3.7 separate body makes body 368 in component "11:1 twin-disc elbow | original geometry"
ref_plane "WorkPlane49" through (0, 0, -17) normal (0, 0, 1) x (1, 0, 0) in component "11:1 twin-disc elbow | original geometry"
sketch "Fixed metal roller pin 6 | profile (2)" plane through (0, 0, -17) normal (0, 0, 1) x (1, 0, 0) in component "11:1 twin-disc elbow | original geometry"
  circle A0 centre (-25.9808, 15) radius 1.5
extrude "Fixed metal roller pin 6'" add sketch "Fixed metal roller pin 6 | profile (2)" along normal blind 34 separate body makes body 369 in component "11:1 twin-disc elbow | original geometry"
ref_plane "WorkPlane50" through (0, 0, -6) normal (0, 0, 1) x (1, 0, 0) in component "11:1 twin-disc elbow | original geometry"
sketch "693ZZ outer race | profile (10)" plane through (0, 0, -6) normal (0, 0, 1) x (1, 0, 0) in component "11:1 twin-disc elbow | original geometry"
  circle A0 centre (-25.9808, 15) radius 4
  circle A1 centre (-25.9808, 15) radius 3
extrude "693ZZ outer race (10)" add sketch "693ZZ outer race | profile (10)" along normal blind 4 separate body makes body 370 in component "11:1 twin-disc elbow | original geometry"
ref_plane "WorkPlane51" through (0, 0, -6) normal (0, 0, 1) x (1, 0, 0) in component "11:1 twin-disc elbow | original geometry"
sketch "693ZZ inner race | profile (10)" plane through (0, 0, -6) normal (0, 0, 1) x (1, 0, 0) in component "11:1 twin-disc elbow | original geometry"
  circle A0 centre (-25.9808, 15) radius 2.5
  circle A1 centre (-25.9808, 15) radius 1.5
extrude "693ZZ inner race (10)" add sketch "693ZZ inner race | profile (10)" along normal blind 4 separate body makes body 371 in component "11:1 twin-disc elbow | original geometry"
ref_plane "WorkPlane52" through (0, 0, -5.85) normal (0, 0, 1) x (1, 0, 0) in component "11:1 twin-disc elbow | original geometry"
sketch "693ZZ shield | profile (10)" plane through (0, 0, -5.85) normal (0, 0, 1) x (1, 0, 0) in component "11:1 twin-disc elbow | original geometry"
  circle A0 centre (-25.9808, 15) radius 3
  circle A1 centre (-25.9808, 15) radius 2.5
extrude "693ZZ shield (10)" add sketch "693ZZ shield | profile (10)" along normal blind 3.7 separate body makes body 372 in component "11:1 twin-disc elbow | original geometry"
ref_plane "WorkPlane53" through (0, 0, 2) normal (0, 0, 1) x (1, 0, 0) in component "11:1 twin-disc elbow | original geometry"
sketch "693ZZ outer race | profile (11)" plane through (0, 0, 2) normal (0, 0, 1) x (1, 0, 0) in component "11:1 twin-disc elbow | original geometry"
  circle A0 centre (-25.9808, 15) radius 4
  circle A1 centre (-25.9808, 15) radius 3
extrude "693ZZ outer race (11)" add sketch "693ZZ outer race | profile (11)" along normal blind 4 separate body makes body 373 in component "11:1 twin-disc elbow | original geometry"
ref_plane "WorkPlane54" through (0, 0, 2) normal (0, 0, 1) x (1, 0, 0) in component "11:1 twin-disc elbow | original geometry"
sketch "693ZZ inner race | profile (11)" plane through (0, 0, 2) normal (0, 0, 1) x (1, 0, 0) in component "11:1 twin-disc elbow | original geometry"
  circle A0 centre (-25.9808, 15) radius 2.5
  circle A1 centre (-25.9808, 15) radius 1.5
extrude "693ZZ inner race (11)" add sketch "693ZZ inner race | profile (11)" along normal blind 4 separate body makes body 374 in component "11:1 twin-disc elbow | original geometry"
ref_plane "WorkPlane55" through (0, 0, 2.15) normal (0, 0, 1) x (1, 0, 0) in component "11:1 twin-disc elbow | original geometry"
sketch "693ZZ shield | profile (11)" plane through (0, 0, 2.15) normal (0, 0, 1) x (1, 0, 0) in component "11:1 twin-disc elbow | original geometry"
  circle A0 centre (-25.9808, 15) radius 3
  circle A1 centre (-25.9808, 15) radius 2.5
extrude "693ZZ shield (11)" add sketch "693ZZ shield | profile (11)" along normal blind 3.7 separate body makes body 375 in component "11:1 twin-disc elbow | original geometry"
ref_plane "WorkPlane56" through (0, 0, -17) normal (0, 0, 1) x (1, 0, 0) in component "11:1 twin-disc elbow | original geometry"
sketch "Fixed metal roller pin 7 | profile (2)" plane through (0, 0, -17) normal (0, 0, 1) x (1, 0, 0) in component "11:1 twin-disc elbow | original geometry"
  circle A0 centre (-30, 0) radius 1.5
extrude "Fixed metal roller pin 7'" add sketch "Fixed metal roller pin 7 | profile (2)" along normal blind 34 separate body makes body 376 in component "11:1 twin-disc elbow | original geometry"
ref_plane "WorkPlane57" through (0, 0, -6) normal (0, 0, 1) x (1, 0, 0) in component "11:1 twin-disc elbow | original geometry"
sketch "693ZZ outer race | profile (12)" plane through (0, 0, -6) normal (0, 0, 1) x (1, 0, 0) in component "11:1 twin-disc elbow | original geometry"
  circle A0 centre (-30, 0) radius 4
  circle A1 centre (-30, 0) radius 3
extrude "693ZZ outer race (12)" add sketch "693ZZ outer race | profile (12)" along normal blind 4 separate body makes body 377 in component "11:1 twin-disc elbow | original geometry"
ref_plane "WorkPlane58" through (0, 0, -6) normal (0, 0, 1) x (1, 0, 0) in component "11:1 twin-disc elbow | original geometry"
sketch "693ZZ inner race | profile (12)" plane through (0, 0, -6) normal (0, 0, 1) x (1, 0, 0) in component "11:1 twin-disc elbow | original geometry"
  circle A0 centre (-30, 0) radius 2.5
  circle A1 centre (-30, 0) radius 1.5
extrude "693ZZ inner race (12)" add sketch "693ZZ inner race | profile (12)" along normal blind 4 separate body makes body 378 in component "11:1 twin-disc elbow | original geometry"
ref_plane "WorkPlane59" through (0, 0, -5.85) normal (0, 0, 1) x (1, 0, 0) in component "11:1 twin-disc elbow | original geometry"
sketch "693ZZ shield | profile (12)" plane through (0, 0, -5.85) normal (0, 0, 1) x (1, 0, 0) in component "11:1 twin-disc elbow | original geometry"
  circle A0 centre (-30, 0) radius 3
  circle A1 centre (-30, 0) radius 2.5
extrude "693ZZ shield (12)" add sketch "693ZZ shield | profile (12)" along normal blind 3.7 separate body makes body 379 in component "11:1 twin-disc elbow | original geometry"
ref_plane "WorkPlane60" through (0, 0, 2) normal (0, 0, 1) x (1, 0, 0) in component "11:1 twin-disc elbow | original geometry"
sketch "693ZZ outer race | profile (13)" plane through (0, 0, 2) normal (0, 0, 1) x (1, 0, 0) in component "11:1 twin-disc elbow | original geometry"
  circle A0 centre (-30, 0) radius 4
  circle A1 centre (-30, 0) radius 3
extrude "693ZZ outer race (13)" add sketch "693ZZ outer race | profile (13)" along normal blind 4 separate body makes body 380 in component "11:1 twin-disc elbow | original geometry"
ref_plane "WorkPlane61" through (0, 0, 2) normal (0, 0, 1) x (1, 0, 0) in component "11:1 twin-disc elbow | original geometry"
sketch "693ZZ inner race | profile (13)" plane through (0, 0, 2) normal (0, 0, 1) x (1, 0, 0) in component "11:1 twin-disc elbow | original geometry"
  circle A0 centre (-30, 0) radius 2.5
  circle A1 centre (-30, 0) radius 1.5
extrude "693ZZ inner race (13)" add sketch "693ZZ inner race | profile (13)" along normal blind 4 separate body makes body 381 in component "11:1 twin-disc elbow | original geometry"
ref_plane "WorkPlane62" through (0, 0, 2.15) normal (0, 0, 1) x (1, 0, 0) in component "11:1 twin-disc elbow | original geometry"
sketch "693ZZ shield | profile (13)" plane through (0, 0, 2.15) normal (0, 0, 1) x (1, 0, 0) in component "11:1 twin-disc elbow | original geometry"
  circle A0 centre (-30, 0) radius 3
  circle A1 centre (-30, 0) radius 2.5
extrude "693ZZ shield (13)" add sketch "693ZZ shield | profile (13)" along normal blind 3.7 separate body makes body 382 in component "11:1 twin-disc elbow | original geometry"
ref_plane "WorkPlane63" through (0, 0, -17) normal (0, 0, 1) x (1, 0, 0) in component "11:1 twin-disc elbow | original geometry"
sketch "Fixed metal roller pin 8 | profile (2)" plane through (0, 0, -17) normal (0, 0, 1) x (1, 0, 0) in component "11:1 twin-disc elbow | original geometry"
  circle A0 centre (-25.9808, -15) radius 1.5
extrude "Fixed metal roller pin 8'" add sketch "Fixed metal roller pin 8 | profile (2)" along normal blind 34 separate body makes body 383 in component "11:1 twin-disc elbow | original geometry"
ref_plane "WorkPlane64" through (0, 0, -6) normal (0, 0, 1) x (1, 0, 0) in component "11:1 twin-disc elbow | original geometry"
sketch "693ZZ outer race | profile (14)" plane through (0, 0, -6) normal (0, 0, 1) x (1, 0, 0) in component "11:1 twin-disc elbow | original geometry"
  circle A0 centre (-25.9808, -15) radius 4
  circle A1 centre (-25.9808, -15) radius 3
extrude "693ZZ outer race (14)" add sketch "693ZZ outer race | profile (14)" along normal blind 4 separate body makes body 384 in component "11:1 twin-disc elbow | original geometry"
ref_plane "WorkPlane65" through (0, 0, -6) normal (0, 0, 1) x (1, 0, 0) in component "11:1 twin-disc elbow | original geometry"